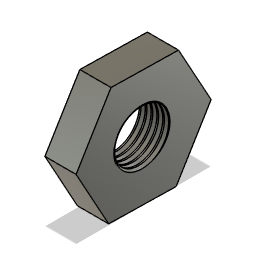
rc-airplanes-trainer-airplane-fusion-parts-nose (Autodesk Fusion 360 archive; units mm, degrees)
design "motor-mount-nut"
Autodesk Fusion 360 part; units mm, degrees
sketch "Sketch1" plane through (0, 0, 0) normal (1, 0, 0) x (0, 0, -1)
  circle A0 centre (0, 0) radius 7.25
  line L0 (17.3171, -0.3443) -> (8.9567, 14.8249)
  line L1 (8.9567, 14.8249) -> (-8.3604, 15.1692)
  line L2 (-8.3604, 15.1692) -> (-17.3171, 0.3443)
  line L3 (-17.3171, 0.3443) -> (-8.9567, -14.8249)
  line L4 (-8.9567, -14.8249) -> (8.3604, -15.1692)
  line L5 (8.3604, -15.1692) -> (17.3171, -0.3443)
  dimension "d1" = 14.5
  dimension "d2" = 15
  constraint coincident A0.centre origin
  measures "d1" diameter of A0
  measures "d2" distance of A0.centre L5
extrude "Extrude1" add sketch "Sketch1" along normal blind 15
thread "Thread2" "ISO Metric profile 15.0 M15x1.5 M15x1.5 6H" major diameter 15.2033 minor diameter 13.5262 pitch 1.5 angle 60 modelled left hand crest width 0.4068 on face at (10, -0.7219, -7.214) crest through (0.375, 0, -6.7631)
sketch "Sketch2" plane through (15, 0, 0) normal (1, 0, 0) x (0, 0, -1)
  line L0 (8.3604, -15.1692) -> (17.3171, -0.3443)
  line L1 (17.3171, -0.3443) -> (8.9567, 14.8249)
  line L2 (8.9567, 14.8249) -> (-8.3604, 15.1692)
  line L3 (-8.3604, 15.1692) -> (-17.3171, 0.3443)
  line L4 (-17.3171, 0.3443) -> (-8.9567, -14.8249)
  line L5 (-8.9567, -14.8249) -> (8.3604, -15.1692)
  spline S0 degree 3 poles (5.0896, 4.4537) (5.7149, 3.8215) (6.2092, 3.0721) (6.8944, 1.4078) (7.0714, 0.506) (7.0735, -1.3357) (6.8908, -2.2578) (6.1778, -4.0012) (5.6471, -4.8026) (4.5631, -5.9036) (4.0981, -6.2743) (3.084, -6.9025) (2.5375, -7.1562) (1.9668, -7.3428) knots 0 0 0 0 0.26677 0.26677 0.539683 0.539683 0.818736 0.818736 1.103927 1.103927 1.281345 1.281345 1.461078 1.461078 1.461078 1.461078
  arc A0 (-1.9668, -7.3428) -> (1.9668, -7.3428) centre (0, 0) ccw
  spline S1 degree 3 poles (-1.9668, -7.3428) (-2.8966, -7.0387) (-3.7588, -6.5578) (-5.232, -5.303) (-5.8339, -4.5474) (-6.7012, -2.8644) (-6.9652, -1.9571) (-7.1249, -0.1126) (-7.027, 0.806) (-6.5901, 2.2032) (-6.3648, 2.7059) (-5.803, 3.64) (-5.4701, 4.069) (-5.0896, 4.4537) knots 0 0 0 0 0.293478 0.293478 0.580806 0.580806 0.861983 0.861983 1.137006 1.137006 1.301997 1.301997 1.464671 1.464671 1.464671 1.464671
  arc A1 (5.0896, 4.4537) -> (-5.0896, 4.4537) centre (0, 0) ccw
  circle A2 centre (0, 0) radius 23.6598
  constraint concentric A0 A2
extrude "Extrude2" cut sketch "Sketch2" against normal blind 7 contours L0 L1 L2 L3 L4 L5 | S0 A0 S1 A1 | A2
scale "Scale1" factor 1.03 about (0, 15.1692, 8.3604) bodies 1
